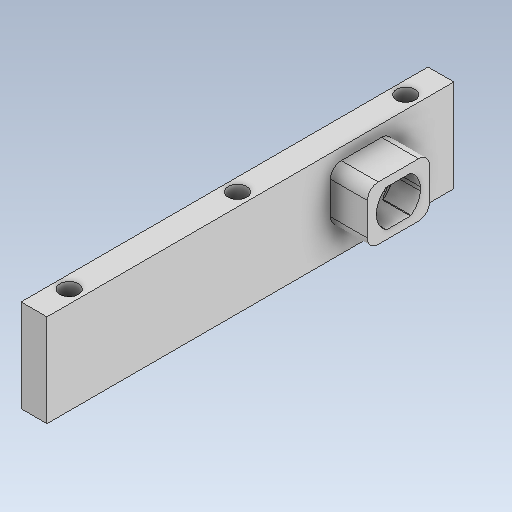
# Autodesk Inventor part: Innneseite_links
Saved by Autodesk Inventor 2026.4 (Build 304435030, 435C)
## iProperties
Created: 2026-11-20
Part Number: Innneseite_links
Material: Generisch
Document SubType Name: Modeling
Designer: weira
Density: 1 g/cm^3
Appearance: Vorgabe
Author: weira
Autodesk Inventor part; units mm, degrees
ref_plane "YZ Plane" through (0, 0, 0) normal (1, 0, 0) x (0, 1, 0)
ref_plane "XZ Plane" through (0, 0, 0) normal (0, 1, 0) x (-1, 0, 0)
ref_plane "XY Plane" through (0, 0, 0) normal (0, 0, 1) x (1, 0, 0)
sketch "Skizze1" plane through (0, 0, 0) normal (1, 0, 0) x (0, 1, 0)
  line L0 (-55, 12.5) -> (55, 12.5)
  line L1 (55, 12.5) -> (55, -12.5)
  line L2 (55, -12.5) -> (-55, -12.5)
  line L3 (-55, -12.5) -> (-55, 12.5)
  line L4 (-55, 12.5) -> (55, -12.5) construction
  line L5 (55, 12.5) -> (-55, -12.5) construction
  point P0 (0, 0)
  dimension "d0" = 25
  dimension "d1" = 110
  constraints: 12 end point, 2 midpoint, 2 parallel, 1 horizontal, 1 perpendicular
  measures "d0" distance between parallel lines of L2 L0
  measures "d1" distance of L0.start L0.end
extrude "Extrusion1" add sketch "Skizze1" along normal blind 7
sketch "Skizze2" plane through (0, 0, 0) normal (-1, 0, 0) x (0, 0, 1)
  line L0 (-12.5, -55) -> (-12.5, 55) projected
  line L1 (12.5, -55) -> (-12.5, -55) projected
  line L2 (12.5, 55) -> (12.5, -55) projected
  line L3 (-12.5, 55) -> (12.5, 55) projected
  line L4 (16.5, -55) -> (16.5, 55)
  line L5 (16.5, 55) -> (-12.5, 55)
  line L6 (-12.5, 55) -> (-12.5, -55)
  line L7 (-12.5, -55) -> (16.5, -55)
  circle A0 centre (2, -30) radius 8.5
  circle A1 centre (2, 30) radius 8.5
  circle A2 centre (2, -30) radius 19 construction
  circle A3 centre (2, 30) radius 19 construction
  line L8 (-12.5, 55) -> (16.5, 55)
  line L9 (16.5, 55) -> (16.5, 50)
  line L10 (16.5, 50) -> (-12.5, 50)
  line L11 (-12.5, 50) -> (-12.5, 55)
  line L12 (16.5, -55) -> (16.5, 55)
  line L13 (-12.5, -55) -> (16.5, -55)
  line L14 (16.5, -55) -> (16.5, -50)
  line L15 (16.5, -50) -> (-12.5, -50)
  line L16 (-12.5, -50) -> (-12.5, -55)
  circle A4 centre (2, -30) radius 20
  circle A5 centre (2, 30) radius 20
  circle A6 centre (2, -30) radius 6.5
  circle A7 centre (2, 30) radius 6.5
  point P0 (0, 0)
  point P1 (0, 0)
  point P2 (2, 49)
  dimension "d10" = 38
  dimension "d4" = 14.5
  dimension "d5" = 14.5
  dimension "d6" = 29
  dimension "d7" = 17
  dimension "d8" = 17
  dimension "d9" = 38
  dimension "d11" = 60
  dimension "d12" = 25
  dimension "d13" = 110
  dimension "d14" = 5
  dimension "d15" = 5
  dimension "d16" = 40
  dimension "d17" = 13
  dimension "d18" = 13
  dimension "d71" = 14.5
  constraints: 26 end point, 9 coincident, 7 centre point, 4 parallel, 2 horizontal, 2 perpendicular, 2 point on line, 1 vertical alignment, 2 other
  measures "d4" distance from line of L4 point (2, -30)
  measures "d5" distance from line of L4 point (2, 30)
  measures "d6" distance between parallel lines of L4 L6
  measures "d7" diameter of A0
  measures "d8" diameter of A1
  measures "d9" diameter of A2
  measures "d11" distance of A1.centre A0.centre
  measures "d12" distance from line of L7 A0.centre
  measures "d13" distance of L4.start L4.end
  measures "d14" distance between parallel lines of L5 L10
  measures "d15" distance between parallel lines of L7 L15
  measures "d16" diameter of A4
  measures "d17" diameter of A7
  measures "d18" diameter of A6
  measures "d71" distance from line of L6 A0.centre
extrude "Extrusion2" cut sketch "Skizze2" against normal blind 5 contours A0 | A6
extrude "Extrusion3" cut sketch "Skizze2" against normal blind 5.2 contours A6
sketch "Skizze3" plane through (0, -55, 12.5) normal (0, 0, 1) x (1, 0, 0)
  line L0 (5, 76.5) -> (5, 93.5) projected
  line L1 (0, 110) -> (0, 0) projected
  line L2 (0, 0) -> (7, 0) projected
  line L3 (7, 110) -> (7, 0) projected
  line L4 (0, 110) -> (7, 110) projected
  line L5 (0, 110) -> (0, 0)
  line L6 (0, 0) -> (7, 0)
  line L7 (7, 110) -> (7, 0)
  line L8 (0, 110) -> (7, 110)
  line L9 (3.5, 0) -> (3.5, 110) construction
  line L10 (2, 93.5) -> (2, 76.5)
  line L11 (2, 33.5) -> (2, 16.5)
  circle A0 centre (3.5, 100.5) radius 2.5 construction
  circle A1 centre (3.5, 9.5) radius 2.5 construction
  line L12 (0, 110) -> (7, 110)
  line L13 (0, 16.5) -> (7, 16.5) construction
  line L14 (0, 93.5) -> (7, 93.5) construction
  line L15 (0, 33.5) -> (7, 33.5) construction
  line L16 (0, 0) -> (0, 110)
  line L17 (0, 76.5) -> (7, 76.5) construction
  line L18 (0, 55) -> (7, 55) construction
  point P0 (0, 55)
  point P1 (3.5, 55)
  dimension "d23" = 7
  dimension "d24" = 3.5
  dimension "d25" = 110
  dimension "d26" = 55
  dimension "d27" = 5
  dimension "d28" = 5
  dimension "d29" = 9.5
  dimension "d30" = 9.5
  constraints: 28 end point, 10 point on line, 5 midpoint, 4 perpendicular, 3 coincident, 2 centre point
  measures "d23" distance between parallel lines of L7 L5
  measures "d24" distance between parallel lines of L5 L9
  measures "d25" distance of L7.start L6.end
  measures "d26" distance from line of L8 point (3.5, 55)
  measures "d27" diameter of A0
  measures "d28" diameter of A1
  measures "d29" distance from line of L6 A1.centre
  measures "d30" distance of point (3.5, 110) A0.centre
hole "Bohrung1" at (3.5, -45.5, 12.5) at (3.5, 45.5, 12.5) at (3.5, 0, 12.5) direction (0, 0, -1) diameter 5 end through all
sketch "Skizze4" plane through (7, 0, 0) normal (1, 0, 0) x (0, 0, -1)
  circle A0 centre (-2, -30) radius 8.5 projected
  line L0 (12.5, -55) -> (12.5, 55) projected
  line L1 (12.5, 55) -> (-12.5, 55) projected
  line L2 (-12.5, 55) -> (-12.5, -55) projected
  line L3 (-12.5, -55) -> (12.5, -55) projected
  line L4 (12.5, 2.2123) -> (12.5, 55)
  arc A1 (-1.4961, 66.3758) -> (-0.9961, 66.8758) centre (-1.4961, 66.8758) ccw
  line L5 (-0.9961, 66.8758) -> (-0.9961, 77.7758)
  arc A2 (-0.9961, 77.7758) -> (-1.4961, 78.2758) centre (-1.4961, 77.7758) ccw
  line L6 (-1.4961, 78.2758) -> (-10.2961, 78.2758)
  arc A3 (-10.2961, 78.2758) -> (-10.7961, 77.7758) centre (-10.2961, 77.7758) ccw
  line L7 (-10.7961, 77.7758) -> (-10.7961, 66.8758)
  arc A4 (-10.7961, 66.8758) -> (-10.2961, 66.3758) centre (-10.2961, 66.8758) ccw
  line L8 (-10.2961, 66.3758) -> (-1.4961, 66.3758)
  circle A5 centre (-8.8961, 76.3258) radius 1.325
  spline S0 degree 3 poles (-5.8961, 74.3258) (-5.645, 74.3258) (-5.4271, 74.2764) (-5.2521, 74.216) (-4.8953, 74.0929) (-4.5738, 73.8767) (-4.3311, 73.5726) (-4.0743, 73.2508) (-3.9035, 72.8091) (-3.8946, 72.3458) (-3.8918, 72.2003) (-3.9043, 72.0437) (-3.9417, 71.8796) (-4.0535, 71.3894) (-4.3969, 70.9004) (-4.8518, 70.6194) (-4.9087, 70.5843) (-4.9674, 70.5521) (-5.0276, 70.5231) (-5.1545, 70.462) (-5.2876, 70.4155) (-5.4237, 70.3831) (-5.5782, 70.3464) (-5.7372, 70.3278) (-5.8961, 70.3274) (-6.1602, 70.3267) (-6.4255, 70.3762) (-6.67, 70.4776) (-6.7025, 70.491) (-6.7341, 70.5052) (-6.7648, 70.52) (-7.234, 70.7459) (-7.4825, 71.0484) (-7.6694, 71.4044) (-7.7488, 71.5557) (-7.8087, 71.7159) (-7.8461, 71.8796) (-7.9389, 72.2862) (-7.9012, 72.7199) (-7.7285, 73.1243) (-7.6663, 73.2701) (-7.5811, 73.4236) (-7.4622, 73.5728) (-7.1454, 73.9706) (-6.6216, 74.2624) (-6.0869, 74.3162) (-6.0516, 74.3197) (-6.0163, 74.3223) (-5.981, 74.3239) (-5.9523, 74.3252) (-5.924, 74.3258) (-5.8961, 74.3258) knots 0.733383 0.733383 0.733383 0.733383 0.811921 0.811921 0.811921 0.972038 0.972038 0.972038 1.141536 1.141536 1.141536 1.194769 1.194769 1.194769 1.353829 1.353829 1.353829 1.373715 1.373715 1.373715 1.415683 1.415683 1.415683 1.46334 1.46334 1.46334 1.542576 1.542576 1.542576 1.553105 1.553105 1.553105 1.714156 1.714156 1.714156 1.782613 1.782613 1.782613 1.952625 1.952625 1.952625 2.013895 2.013895 2.013895 2.177242 2.177242 2.177242 2.187997 2.187997 2.187997 2.196723 2.196723 2.196723 2.196723
  circle A6 centre (-2.8961, 68.3258) radius 1.325
  arc A7 (-6.4, 35.95) -> (-6.9, 35.45) centre (-6.4, 35.45) ccw
  circle A8 centre (-5, 34) radius 1.325
  circle A9 centre (1, 26) radius 1.325
  arc A10 (-6.9, 24.55) -> (-6.4, 24.05) centre (-6.4, 24.55) ccw
  arc A11 (2.9, 35.45) -> (2.4, 35.95) centre (2.4, 35.45) ccw
  arc A12 (2.4, 24.05) -> (2.9, 24.55) centre (2.4, 24.55) ccw
  spline S1 degree 3 poles (-2, 32) (-1.749, 32) (-1.531, 31.9506) (-1.356, 31.8902) (-0.9992, 31.7671) (-0.6777, 31.5509) (-0.4351, 31.2469) (-0.1782, 30.925) (-0.0074, 30.4833) (0.0014, 30.02) (0.0042, 29.8745) (-0.0082, 29.7179) (-0.0456, 29.5538) (-0.1575, 29.0636) (-0.5009, 28.5747) (-0.9557, 28.2937) (-1.0126, 28.2585) (-1.0713, 28.2263) (-1.1315, 28.1973) (-1.2584, 28.1362) (-1.3915, 28.0897) (-1.5276, 28.0573) (-1.6821, 28.0206) (-1.8411, 28.002) (-2, 28.0016) (-2.2641, 28.0009) (-2.5294, 28.0504) (-2.7739, 28.1518) (-2.8064, 28.1652) (-2.838, 28.1794) (-2.8687, 28.1942) (-3.3379, 28.4201) (-3.5864, 28.7226) (-3.7733, 29.0786) (-3.8527, 29.2299) (-3.9126, 29.3901) (-3.95, 29.5538) (-4.0429, 29.9604) (-4.0051, 30.3941) (-3.8324, 30.7986) (-3.7702, 30.9443) (-3.685, 31.0978) (-3.5661, 31.247) (-3.2493, 31.6448) (-2.7255, 31.9366) (-2.1908, 31.9904) (-2.1556, 31.9939) (-2.1203, 31.9965) (-2.0849, 31.9981) (-2.0562, 31.9994) (-2.0279, 32) (-2, 32) knots 0.733383 0.733383 0.733383 0.733383 0.811921 0.811921 0.811921 0.972038 0.972038 0.972038 1.141536 1.141536 1.141536 1.194769 1.194769 1.194769 1.353829 1.353829 1.353829 1.373715 1.373715 1.373715 1.415683 1.415683 1.415683 1.46334 1.46334 1.46334 1.542576 1.542576 1.542576 1.553105 1.553105 1.553105 1.714156 1.714156 1.714156 1.782613 1.782613 1.782613 1.952625 1.952625 1.952625 2.013895 2.013895 2.013895 2.177242 2.177242 2.177242 2.187997 2.187997 2.187997 2.196723 2.196723 2.196723 2.196723
  line L9 (-6.4, 24.05) -> (2.4, 24.05)
  line L10 (2.4, 35.95) -> (-6.4, 35.95)
  line L11 (2.9, 24.55) -> (2.9, 35.45)
  line L12 (-6.9, 35.45) -> (-6.9, 24.55)
  point P0 (0, 0)
  point P1 (-2, 30)
  point P2 (-5.8961, 72.3258)
  point P3 (-5.8961, 74.3258)
  point P4 (-2, 30)
  point P5 (-2, 32)
  dimension "d42" = 25
  dimension "d72" = 60
  dimension "d73" = 14.5
  constraints: 18 end point, 16 point on circle, 12 centre point, 2 other
  measures "d42" distance of L0.end L1.end
  measures "d72" distance of A0.centre point (-2, 30)
  measures "d73" distance from line of L0 point (-2, 30)
extrude "Extrusion4" cut sketch "Skizze4" against normal through all contours L10 A11 L11 A12 L9 A10 L12 A7 | A8 | A9 | S1
sketch "Skizze5" plane through (7, 0, 0) normal (1, 0, 0) x (0, 0, -1)
  line L0 (2.9, 35.45) -> (2.9, 24.55) projected
  arc A0 (2.4, 24.05) -> (2.9, 24.55) centre (2.4, 24.55) ccw projected
  line L1 (2.4, 24.05) -> (-6.4, 24.05) projected
  arc A1 (-6.9, 24.55) -> (-6.4, 24.05) centre (-6.4, 24.55) ccw projected
  line L2 (-6.9, 24.55) -> (-6.9, 35.45) projected
  arc A2 (-6.4, 35.95) -> (-6.9, 35.45) centre (-6.4, 35.45) ccw projected
  line L3 (-6.4, 35.95) -> (2.4, 35.95) projected
  arc A3 (2.9, 35.45) -> (2.4, 35.95) centre (2.4, 35.45) ccw projected
  line L4 (12.5, -55) -> (12.5, 55) projected
  line L5 (12.5, 55) -> (-12.5, 55) projected
  line L6 (-12.5, 55) -> (-12.5, -55) projected
  line L7 (-12.5, -55) -> (12.5, -55) projected
  line L8 (-9.3, 35.45) -> (-9.3, 24.55)
  arc A4 (-9.3, 24.55) -> (-6.4, 21.65) centre (-6.4, 24.55) ccw
  line L9 (-6.4, 21.65) -> (2.4, 21.65)
  arc A5 (2.4, 21.65) -> (5.3, 24.55) centre (2.4, 24.55) ccw
  line L10 (5.3, 24.55) -> (5.3, 35.45)
  arc A6 (5.3, 35.45) -> (2.4, 38.35) centre (2.4, 35.45) ccw
  line L11 (2.4, 38.35) -> (-6.4, 38.35)
  arc A7 (-6.4, 38.35) -> (-9.3, 35.45) centre (-6.4, 35.45) ccw
  point P0 (0, 0)
  dimension "d74" = 2.4
  constraints: 8 end point, 8 point on circle, 4 centre point, 7 other
  measures "d74" distance between parallel lines of L2 L8
extrude "Extrusion5" add sketch "Skizze5" along normal blind 1.9 contours A7 L11 A6 L10 A5 L9 A4 L8
sketch "Skizze6" plane through (8.9, 0, 0) normal (1, 0, 0) x (0, 0, -1)
  spline S0 degree 3 poles (1.1324, 61.7724) (2.9383, 61.9247) (4.6477, 62.9496) (5.6324, 64.4761) knots 0 0 0 0 1 1 1 1
  spline S1 degree 3 poles (0.1324, 61.7724) (0.2987, 61.7584) (0.4655, 61.7514) (0.7993, 61.7514) (0.9661, 61.7584) (1.1324, 61.7724) knots 0 0 0 0 0.5 0.5 1 1 1 1
  spline S2 degree 3 poles (-4.3676, 64.4761) (-3.3829, 62.9496) (-1.6736, 61.9247) (0.1324, 61.7724) knots 0 0 0 0 1 1 1 1
  line L0 (5.6324, 64.4761) -> (5.6324, 70.9267)
  spline S3 degree 3 poles (5.6324, 70.9267) (4.6477, 72.4532) (2.9383, 73.4781) (1.1324, 73.6304) knots 0 0 0 0 1 1 1 1
  spline S4 degree 3 poles (0.1324, 73.6304) (-1.6736, 73.4781) (-3.3829, 72.4532) (-4.3676, 70.9267) knots 0 0 0 0 1 1 1 1
  line L1 (-4.3676, 70.9267) -> (-4.3676, 64.4761)
  spline S5 degree 3 poles (1.1324, 73.6304) (0.9661, 73.6444) (0.7993, 73.6514) (0.4655, 73.6514) (0.2987, 73.6444) (0.1324, 73.6304) knots 0 0 0 0 0.5 0.5 1 1 1 1
  line L2 (-28.2501, 0.1383) -> (-27.7556, -0.2574) construction
  spline S6 degree 3 poles (-16.7641, 79.1019) (-16.9304, 79.1159) (-17.0972, 79.1229) (-17.431, 79.1229) (-17.5978, 79.1159) (-17.7641, 79.1019) knots 0 0 0 0 0.5 0.5 1 1 1 1
  spline S7 degree 3 poles (-17.7641, 79.1019) (-19.5701, 78.9496) (-21.2794, 77.9247) (-22.2641, 76.3982) knots 0 0 0 0 1 1 1 1
  spline S8 degree 3 poles (-12.2641, 76.3982) (-13.2488, 77.9247) (-14.9582, 78.9496) (-16.7641, 79.1019) knots 0 0 0 0 1 1 1 1
  line L3 (-22.2641, 76.3982) -> (-22.2641, 69.9476)
  spline S9 degree 3 poles (-17.7641, 67.244) (-17.5978, 67.2299) (-17.431, 67.2229) (-17.0972, 67.2229) (-16.9304, 67.2299) (-16.7641, 67.244) knots 0 0 0 0 0.5 0.5 1 1 1 1
  spline S10 degree 3 poles (-22.2641, 69.9476) (-21.2794, 68.4211) (-19.5701, 67.3963) (-17.7641, 67.244) knots 0 0 0 0 1 1 1 1
  spline S11 degree 3 poles (-16.7641, 67.244) (-14.9582, 67.3963) (-13.2488, 68.4211) (-12.2641, 69.9476) knots 0 0 0 0 1 1 1 1
  line L4 (-12.2641, 69.9476) -> (-12.2641, 76.3982)
  line L5 (-17.2641, 73.1729) -> (-15.0095, 73.1729) construction
  line L6 (-17.2641, 73.1729) -> (-17.2641, 69.8514) construction
  line L7 (-12.3641, 69.2746) -> (-15.396, 67.2229)
  line L8 (-22.1641, 69.2746) -> (-19.1323, 67.2229)
  line L9 (-12.3641, 77.0713) -> (-15.396, 79.1229)
  line L10 (-22.1641, 77.0713) -> (-19.1323, 79.1229)
  line L11 (-12.8641, 67.7229) -> (-21.6641, 78.6229) construction
  line L12 (-12.8641, 78.6229) -> (-21.6641, 67.7229) construction
  arc A0 (-9.3, 24.55) -> (-6.4, 21.65) centre (-6.4, 24.55) ccw
  line L13 (-6.4, 21.65) -> (2.4, 21.65)
  arc A1 (2.4, 21.65) -> (5.3, 24.55) centre (2.4, 24.55) ccw
  line L14 (5.3, 24.55) -> (5.3, 35.45)
  arc A2 (5.3, 35.45) -> (2.4, 38.35) centre (2.4, 35.45) ccw
  line L15 (2.4, 38.35) -> (-6.4, 38.35)
  arc A3 (-6.4, 38.35) -> (-9.3, 35.45) centre (-6.4, 35.45) ccw
  line L16 (-9.3, 35.45) -> (-9.3, 24.55)
  line L17 (-6.4, 35.95) -> (2.4, 35.95)
  arc A4 (2.9, 35.45) -> (2.4, 35.95) centre (2.4, 35.45) ccw
  line L18 (2.9, 35.45) -> (2.9, 24.55)
  arc A5 (2.4, 24.05) -> (2.9, 24.55) centre (2.4, 24.55) ccw
  line L19 (2.4, 24.05) -> (-6.4, 24.05)
  arc A6 (-6.9, 24.55) -> (-6.4, 24.05) centre (-6.4, 24.55) ccw
  line L20 (-6.9, 24.55) -> (-6.9, 35.45)
  arc A7 (-6.4, 35.95) -> (-6.9, 35.45) centre (-6.4, 35.45) ccw
  line L21 (-6.4, 24.55) -> (2.4, 35.45) construction
  line L22 (2.4, 24.55) -> (-6.4, 35.45) construction
  spline S12 degree 3 poles (-2.5, 24.071) (-2.3337, 24.057) (-2.1669, 24.05) (-1.8331, 24.05) (-1.6663, 24.057) (-1.5, 24.071) knots 0 0 0 0 0.5 0.5 1 1 1 1
  spline S13 degree 3 poles (-1.5, 24.071) (0.306, 24.2233) (2.0153, 25.2482) (3, 26.7747) knots 0 0 0 0 1 1 1 1
  line L23 (-2, 30) -> (0.2547, 30) construction
  line L24 (-2, 30) -> (-2, 26.6784) construction
  line L25 (-6.9, 26.1017) -> (-3.8681, 24.05)
  spline S14 degree 3 poles (-7, 26.7747) (-6.0153, 25.2482) (-4.306, 24.2234) (-2.5, 24.071) knots 0 0 0 0 1 1 1 1
  line L26 (3, 26.7747) -> (3, 33.2253)
  line L27 (2.9, 33.8983) -> (-0.1319, 35.95)
  spline S15 degree 3 poles (3, 33.2253) (2.0153, 34.7518) (0.306, 35.7767) (-1.5, 35.929) knots 0 0 0 0 1 1 1 1
  line L28 (2.4, 24.55) -> (-6.4, 35.45) construction
  line L29 (2.4, 35.45) -> (-6.4, 24.55) construction
  spline S16 degree 3 poles (-1.5, 35.929) (-1.6663, 35.943) (-1.8331, 35.95) (-2.1669, 35.95) (-2.3337, 35.943) (-2.5, 35.929) knots 0 0 0 0 0.5 0.5 1 1 1 1
  spline S17 degree 3 poles (-2.5, 35.929) (-4.306, 35.7766) (-6.0153, 34.7518) (-7, 33.2253) knots 0 0 0 0 1 1 1 1
  line L30 (-7, 33.2253) -> (-7, 26.7747)
  line L31 (2.9, 26.1017) -> (-0.1319, 24.05)
  line L32 (-6.9, 33.8983) -> (-3.8681, 35.95)
  point P0 (0, 0)
  point P1 (0.6324, 67.7014)
  point P2 (-28.0028, -0.0595)
  point P3 (-17.2641, 73.1729)
  point P4 (-2, 30)
  point P5 (-2, 30)
  point P6 (2.9, 33.375)
  point P7 (2.9, 26.625)
  point P8 (-6.9, 26.625)
  point P9 (-6.9, 33.375)
  constraints: 50 end point, 12 symmetric about line, 6 horizontal alignment, 4 midpoint, 48 other
extrude "Extrusion6" cut sketch "Skizze6" against normal through all contours S16 S15 L18 S13 S12 S14 L20 S17 | L20 S14 L30 S17 | S15 L26 S13 L18
extrude "Extrusion7" add sketch "Skizze6" along normal blind 0.2 contours L16 A3 L15 A2 L14 A1 L13 A0 | L17 L32 L20 A7 | L17 A4 L18 L27 | L25 L19 A6 L20 | L18 A5 L19 L31
sketch "Skizze8" plane through (5, -30, 2) normal (-1, 0, 0) x (0, 0, 1)
  circle A0 centre (0, 0) radius 6.5 projected
  circle A1 centre (0, 0) radius 8.5 projected
  line L0 (8.5, 0) -> (2.6266, -8.084)
  line L1 (2.6266, -8.084) -> (-6.8766, -4.9962)
  line L2 (-6.8766, -4.9962) -> (-6.8766, 4.9962)
  line L3 (-6.8766, 4.9962) -> (2.6266, 8.084)
  line L4 (2.6266, 8.084) -> (8.5, 0)
  point P0 (-2, 30)
  constraints: 10 end point, 1 coincident, 1 horizontal alignment, 12 other
extrude "Extrusion9" cut sketch "Skizze8" against normal up to surface (0.2 mm away) contours L0 L1 L2 L3 L4
sketch "Skizze9" plane through (9.1, 0, 0) normal (1, 0, 0) x (0, 0, -1)
  line L0 (-6.4, 21.65) -> (2.4, 21.65)
  arc A0 (2.4, 21.65) -> (5.3, 24.55) centre (2.4, 24.55) ccw
  line L1 (5.3, 24.55) -> (5.3, 35.45)
  arc A1 (5.3, 35.45) -> (2.4, 38.35) centre (2.4, 35.45) ccw
  line L2 (2.4, 38.35) -> (-6.4, 38.35)
  arc A2 (-6.4, 38.35) -> (-9.3, 35.45) centre (-6.4, 35.45) ccw
  line L3 (-9.3, 35.45) -> (-9.3, 24.55)
  arc A3 (-9.3, 24.55) -> (-6.4, 21.65) centre (-6.4, 24.55) ccw
  line L4 (-3.8681, 35.95) -> (-0.1319, 35.95)
  line L5 (-0.1319, 35.95) -> (2.9, 33.8983)
  line L6 (2.9, 33.8983) -> (2.9, 33.375)
  arc A4 (3, 33.2253) -> (2.9, 33.375) centre (-1.7435, 30.1653) ccw
  line L7 (3, 33.2253) -> (3, 26.7747)
  arc A5 (2.9, 26.625) -> (3, 26.7747) centre (-1.7435, 29.8347) ccw
  line L8 (2.9, 26.625) -> (2.9, 26.1017)
  line L9 (2.9, 26.1017) -> (-0.1319, 24.05)
  line L10 (-0.1319, 24.05) -> (-3.8681, 24.05)
  line L11 (-3.8681, 24.05) -> (-6.9, 26.1017)
  line L12 (-6.9, 26.1017) -> (-6.9, 26.625)
  arc A6 (-7, 26.7747) -> (-6.9, 26.625) centre (-2.2565, 29.8348) ccw
  line L13 (-7, 26.7747) -> (-7, 33.2253)
  arc A7 (-6.9, 33.375) -> (-7, 33.2253) centre (-2.2564, 30.1651) ccw
  line L14 (-6.9, 33.375) -> (-6.9, 33.8983)
  line L15 (-6.9, 33.8983) -> (-3.8681, 35.95)
  spline S0 degree 3 poles (10.6773, 97.9027) (12.4832, 98.055) (14.1926, 99.0799) (15.1773, 100.6064) knots 0 0 0 0 1 1 1 1
  spline S1 degree 3 poles (9.6773, 97.9027) (9.8436, 97.8887) (10.0104, 97.8817) (10.3442, 97.8817) (10.511, 97.8887) (10.6773, 97.9027) knots 0 0 0 0 0.5 0.5 1 1 1 1
  spline S2 degree 3 poles (5.1773, 100.6064) (6.162, 99.0799) (7.8713, 98.055) (9.6773, 97.9027) knots 0 0 0 0 1 1 1 1
  line L16 (15.1773, 100.6064) -> (15.1773, 107.057)
  spline S3 degree 3 poles (15.1773, 107.057) (14.1926, 108.5835) (12.4832, 109.6084) (10.6773, 109.7607) knots 0 0 0 0 1 1 1 1
  spline S4 degree 3 poles (9.6773, 109.7607) (7.8713, 109.6084) (6.162, 108.5835) (5.1773, 107.057) knots 0 0 0 0 1 1 1 1
  line L17 (5.1773, 107.057) -> (5.1773, 100.6064)
  spline S5 degree 3 poles (10.6773, 109.7607) (10.511, 109.7747) (10.3442, 109.7817) (10.0104, 109.7817) (9.8436, 109.7747) (9.6773, 109.7607) knots 0 0 0 0 0.5 0.5 1 1 1 1
  line L18 (-18.7052, 36.2686) -> (-18.2107, 35.8729) construction
  spline S6 degree 3 poles (-8.2192, 103.3743) (-8.053, 103.3602) (-7.8861, 103.3532) (-7.5523, 103.3532) (-7.3855, 103.3602) (-7.2192, 103.3743) knots 0 0 0 0 0.5 0.5 1 1 1 1
  spline S7 degree 3 poles (-7.2192, 103.3743) (-5.4133, 103.5266) (-3.7039, 104.5514) (-2.7192, 106.0779) knots 0 0 0 0 1 1 1 1
  line L19 (-7.7192, 109.3032) -> (-5.4646, 109.3032) construction
  line L20 (-7.7192, 109.3032) -> (-7.7192, 105.9817) construction
  line L21 (-12.6192, 105.4049) -> (-9.5874, 103.3532)
  spline S8 degree 3 poles (-12.7192, 106.0779) (-11.7345, 104.5514) (-10.0252, 103.5266) (-8.2192, 103.3743) knots 0 0 0 0 1 1 1 1
  line L22 (-2.7192, 106.0779) -> (-2.7192, 112.5285)
  line L23 (-2.8192, 113.2016) -> (-5.8511, 115.2532)
  spline S9 degree 3 poles (-2.7192, 112.5285) (-3.7039, 114.055) (-5.4133, 115.0799) (-7.2192, 115.2322) knots 0 0 0 0 1 1 1 1
  line L24 (-3.3192, 103.8532) -> (-12.1192, 114.7532) construction
  line L25 (-3.3192, 114.7532) -> (-12.1192, 103.8532) construction
  spline S10 degree 3 poles (-7.2192, 115.2322) (-7.3855, 115.2462) (-7.5523, 115.2532) (-7.8861, 115.2532) (-8.053, 115.2462) (-8.2192, 115.2322) knots 0 0 0 0 0.5 0.5 1 1 1 1
  spline S11 degree 3 poles (-8.2192, 115.2322) (-10.0252, 115.0799) (-11.7345, 114.055) (-12.7192, 112.5285) knots 0 0 0 0 1 1 1 1
  line L26 (-12.7192, 112.5285) -> (-12.7192, 106.0779)
  line L27 (-2.8192, 105.4049) -> (-5.8511, 103.3532)
  line L28 (-12.6192, 113.2016) -> (-9.5874, 115.2532)
  arc A8 (0.2449, 60.6803) -> (3.1449, 57.7803) centre (3.1449, 60.6803) ccw
  line L29 (3.1449, 57.7803) -> (11.9449, 57.7803)
  arc A9 (11.9449, 57.7803) -> (14.8449, 60.6803) centre (11.9449, 60.6803) ccw
  line L30 (14.8449, 60.6803) -> (14.8449, 71.5803)
  arc A10 (14.8449, 71.5803) -> (11.9449, 74.4803) centre (11.9449, 71.5803) ccw
  line L31 (11.9449, 74.4803) -> (3.1449, 74.4803)
  arc A11 (3.1449, 74.4803) -> (0.2449, 71.5803) centre (3.1449, 71.5803) ccw
  line L32 (0.2449, 71.5803) -> (0.2449, 60.6803)
  line L33 (3.1449, 72.0803) -> (11.9449, 72.0803)
  arc A12 (12.4449, 71.5803) -> (11.9449, 72.0803) centre (11.9449, 71.5803) ccw
  line L34 (12.4449, 71.5803) -> (12.4449, 60.6803)
  arc A13 (11.9449, 60.1803) -> (12.4449, 60.6803) centre (11.9449, 60.6803) ccw
  line L35 (11.9449, 60.1803) -> (3.1449, 60.1803)
  arc A14 (2.6449, 60.6803) -> (3.1449, 60.1803) centre (3.1449, 60.6803) ccw
  line L36 (2.6449, 60.6803) -> (2.6449, 71.5803)
  arc A15 (3.1449, 72.0803) -> (2.6449, 71.5803) centre (3.1449, 71.5803) ccw
  line L37 (3.1449, 60.6803) -> (11.9449, 71.5803) construction
  line L38 (11.9449, 60.6803) -> (3.1449, 71.5803) construction
  line L39 (2.6449, 70.0286) -> (5.6768, 72.0803)
  spline S12 degree 3 poles (7.0449, 72.0593) (5.2389, 71.9069) (3.5296, 70.8821) (2.5449, 69.3556) knots 0 0 0 0 1 1 1 1
  spline S13 degree 3 poles (8.0449, 72.0593) (7.8786, 72.0733) (7.7118, 72.0803) (7.378, 72.0803) (7.2112, 72.0733) (7.0449, 72.0593) knots 0 0 0 0 0.5 0.5 1 1 1 1
  spline S14 degree 3 poles (12.5449, 69.3556) (11.5602, 70.8821) (9.8509, 71.907) (8.0449, 72.0593) knots 0 0 0 0 1 1 1 1
  line L40 (12.4449, 70.0286) -> (9.413, 72.0803)
  line L41 (7.5449, 66.1303) -> (9.7995, 66.1303) construction
  line L42 (12.5449, 62.905) -> (12.5449, 69.3556)
  line L43 (2.5449, 69.3556) -> (2.5449, 62.905)
  line L44 (11.9449, 71.5803) -> (3.1449, 60.6803) construction
  line L45 (11.9449, 60.6803) -> (3.1449, 71.5803) construction
  line L46 (7.5449, 66.1303) -> (7.5449, 62.8087) construction
  spline S15 degree 3 poles (7.0449, 60.2013) (7.2112, 60.1873) (7.378, 60.1803) (7.7118, 60.1803) (7.8786, 60.1873) (8.0449, 60.2013) knots 0 0 0 0 0.5 0.5 1 1 1 1
  line L47 (2.6449, 62.232) -> (5.6768, 60.1803)
  spline S16 degree 3 poles (2.5449, 62.905) (3.5296, 61.3785) (5.2389, 60.3537) (7.0449, 60.2013) knots 0 0 0 0 1 1 1 1
  line L48 (12.4449, 62.232) -> (9.413, 60.1803)
  spline S17 degree 3 poles (8.0449, 60.2013) (9.8509, 60.3536) (11.5602, 61.3785) (12.5449, 62.905) knots 0 0 0 0 1 1 1 1
  arc A16 (-9.3, 24.55) -> (-6.4, 21.65) centre (-6.4, 24.55) ccw
  line L49 (-6.4, 21.65) -> (2.4, 21.65)
  arc A17 (2.4, 21.65) -> (5.3, 24.55) centre (2.4, 24.55) ccw
  line L50 (5.3, 24.55) -> (5.3, 35.45)
  arc A18 (5.3, 35.45) -> (2.4, 38.35) centre (2.4, 35.45) ccw
  line L51 (2.4, 38.35) -> (-6.4, 38.35)
  arc A19 (-6.4, 38.35) -> (-9.3, 35.45) centre (-6.4, 35.45) ccw
  line L52 (-9.3, 35.45) -> (-9.3, 24.55)
  line L53 (-6.4, 35.95) -> (2.4, 35.95)
  arc A20 (2.9, 35.45) -> (2.4, 35.95) centre (2.4, 35.45) ccw
  line L54 (2.9, 35.45) -> (2.9, 24.55)
  arc A21 (2.4, 24.05) -> (2.9, 24.55) centre (2.4, 24.55) ccw
  line L55 (2.4, 24.05) -> (-6.4, 24.05)
  arc A22 (-6.9, 24.55) -> (-6.4, 24.05) centre (-6.4, 24.55) ccw
  line L56 (-6.9, 24.55) -> (-6.9, 35.45)
  arc A23 (-6.4, 35.95) -> (-6.9, 35.45) centre (-6.4, 35.45) ccw
  line L57 (-6.4, 24.55) -> (2.4, 35.45) construction
  line L58 (2.4, 24.55) -> (-6.4, 35.45) construction
  line L59 (-6.9, 33.8983) -> (-3.8681, 35.95)
  spline S18 degree 3 poles (-2.5, 35.929) (-4.306, 35.7766) (-6.0153, 34.7518) (-7, 33.2253) knots 0 0 0 0 1 1 1 1
  spline S19 degree 3 poles (-1.5, 35.929) (-1.6663, 35.943) (-1.8331, 35.95) (-2.1669, 35.95) (-2.3337, 35.943) (-2.5, 35.929) knots 0 0 0 0 0.5 0.5 1 1 1 1
  spline S20 degree 3 poles (3, 33.2253) (2.0153, 34.7518) (0.306, 35.7767) (-1.5, 35.929) knots 0 0 0 0 1 1 1 1
  line L60 (2.9, 33.8983) -> (-0.1319, 35.95)
  line L61 (-2, 30) -> (0.2547, 30) construction
  line L62 (3, 26.7747) -> (3, 33.2253)
  line L63 (-7, 33.2253) -> (-7, 26.7747)
  line L64 (2.4, 35.45) -> (-6.4, 24.55) construction
  line L65 (2.4, 24.55) -> (-6.4, 35.45) construction
  line L66 (-2, 30) -> (-2, 26.6784) construction
  spline S21 degree 3 poles (-2.5, 24.071) (-2.3337, 24.057) (-2.1669, 24.05) (-1.8331, 24.05) (-1.6663, 24.057) (-1.5, 24.071) knots 0 0 0 0 0.5 0.5 1 1 1 1
  line L67 (-6.9, 26.1017) -> (-3.8681, 24.05)
  spline S22 degree 3 poles (-7, 26.7747) (-6.0153, 25.2482) (-4.306, 24.2234) (-2.5, 24.071) knots 0 0 0 0 1 1 1 1
  line L68 (2.9, 26.1017) -> (-0.1319, 24.05)
  spline S23 degree 3 poles (-1.5, 24.071) (0.306, 24.2233) (2.0153, 25.2482) (3, 26.7747) knots 0 0 0 0 1 1 1 1
  point P0 (0, 0)
  point P1 (9.5449, 36.1303)
  point P2 (10.1773, 103.8317)
  point P3 (-18.4579, 36.0708)
  point P4 (-7.7192, 109.3032)
  point P5 (7.5449, 66.1303)
  point P6 (7.5449, 66.1303)
  point P7 (12.4449, 69.5053)
  point P8 (12.4449, 62.7553)
  point P9 (2.6449, 62.7553)
  point P10 (2.6449, 69.5053)
  point P11 (-2, 30)
  point P12 (-2, 30)
  point P13 (-6.9, 33.375)
  point P14 (2.9, 26.625)
  constraints: 106 end point, 32 point on circle, 18 symmetric about line, 16 centre point, 8 horizontal alignment, 6 midpoint, 64 other
extrude "Extrusion10" add sketch "Skizze9" along normal blind 7.9 contours A3 L3 A2 L2 A1 L1 A0 L0 | L4 S19 S18 L14 L15 | L15 L56 A23 L53 | L4 L5 L6 S20 S19 | L53 A20 L54 L5 | S22 S21 L10 L11 L12 | L8 L9 L10 S21 S23 | L11 L55 A22 L56 | L54 A21 L55 L9
sketch "Skizze10" plane through (0, 0, 0) normal (-1, 0, 0) x (0, 0, 1)
  spline S0 degree 5 poles (-3, 33.2253) (-2.9805, 33.2556) (-2.9607, 33.2857) (-2.9407, 33.3156) (-2.9205, 33.3454) (-2.9, 33.375) knots 0 0 0 0 0 0 1 1 1 1 1 1 projected
  line L0 (-2.9, 33.375) -> (-2.9, 35.45) projected
  arc A0 (-2.4, 35.95) -> (-2.9, 35.45) centre (-2.4, 35.45) ccw projected
  line L1 (-2.4, 35.95) -> (6.4, 35.95) projected
  arc A1 (6.9, 35.45) -> (6.4, 35.95) centre (6.4, 35.45) ccw projected
  line L2 (6.9, 35.45) -> (6.9, 33.375) projected
  spline S1 degree 5 poles (6.9, 33.375) (6.9205, 33.3454) (6.9407, 33.3156) (6.9607, 33.2857) (6.9805, 33.2556) (7, 33.2253) knots 0 0 0 0 0 0 1 1 1 1 1 1 projected
  line L3 (7, 33.2253) -> (7, 26.7747) projected
  spline S2 degree 5 poles (7, 26.7747) (6.9805, 26.7444) (6.9607, 26.7143) (6.9407, 26.6844) (6.9205, 26.6546) (6.9, 26.625) knots 0 0 0 0 0 0 1 1 1 1 1 1 projected
  line L4 (6.9, 26.625) -> (6.9, 24.55) projected
  arc A2 (6.4, 24.05) -> (6.9, 24.55) centre (6.4, 24.55) ccw projected
  line L5 (6.4, 24.05) -> (-2.4, 24.05) projected
  arc A3 (-2.9, 24.55) -> (-2.4, 24.05) centre (-2.4, 24.55) ccw projected
  line L6 (-2.9, 24.55) -> (-2.9, 26.625) projected
  spline S3 degree 5 poles (-2.9, 26.625) (-2.9205, 26.6546) (-2.9407, 26.6844) (-2.9607, 26.7143) (-2.9805, 26.7444) (-3, 26.7747) knots 0 0 0 0 0 0 1 1 1 1 1 1 projected
  line L7 (-3, 26.7747) -> (-3, 33.2253) projected
  circle A4 centre (2, -30) radius 8.5 projected
  line L8 (-12.5, -55) -> (-12.5, 55) projected
  line L9 (12.5, -55) -> (-12.5, -55) projected
  line L10 (12.5, 55) -> (12.5, -55) projected
  line L11 (-12.5, 55) -> (12.5, 55) projected
  line L12 (6.4, 35.45) -> (-2.4, 24.55) construction
  line L13 (6.4, 24.55) -> (-2.4, 35.45) construction
  line L14 (6.5, 36) -> (-2.5, 36)
  line L15 (-3, 35.5) -> (-3, 24.5)
  line L16 (-2.5, 24) -> (6.5, 24)
  line L17 (7, 24.5) -> (7, 35.5)
  line L18 (7, 36) -> (-3, 24) construction
  line L19 (-3, 36) -> (7, 24) construction
  arc A5 (7, 35.5) -> (6.5, 36) centre (6.5, 35.5) ccw
  arc A6 (-2.5, 36) -> (-3, 35.5) centre (-2.5, 35.5) ccw
  arc A7 (-3, 24.5) -> (-2.5, 24) centre (-2.5, 24.5) ccw
  arc A8 (6.5, 24) -> (7, 24.5) centre (6.5, 24.5) ccw
  point P0 (0, 0)
  point P1 (2, 30)
  point P2 (-3, 26.7747)
  point P3 (7, 26.7747)
  point P4 (7, 33.2253)
  point P5 (-3, 33.2253)
  dimension "d77" = 11.9
  dimension "d78" = 10
  dimension "d79" = 12
  dimension "d80" = 0.5
  dimension "d81" = 0.5
  constraints: 16 end point, 8 point on circle, 8 point on line, 8 tangent, 4 centre point, 3 midpoint, 2 equal radius, 2 parallel, 1 horizontal, 1 perpendicular, 4 other
  measures "d77" distance between parallel lines of L5 L1
  measures "d78" distance of L18.end L19.end
  measures "d79" distance between parallel lines of L16 L14
  measures "d80" radius of A5
  measures "d81" radius of A6
extrude "Extrusion11" cut sketch "Skizze10" against normal up to surface (8.9 mm away) contours L15 A6 L14 A5 L17 S1 L2 A1 L1 A0 L0 S0 | S3 L6 A3 L5 A2 L4 S2 L17 A8 L16 A7 L15
sketch "Skizze11" plane through (8.9, 0, 0) normal (-1, 0, 0) x (0, 0, 1)
  line L0 (6.9, 33.375) -> (6.9, 33.8983) projected
  line L1 (6.9, 33.8983) -> (3.8681, 35.95) projected
  line L2 (3.8681, 35.95) -> (2, 35.95) projected
  arc A0 (2.5, 35.929) -> (2, 35.95) centre (2, 30) ccw projected
  line L3 (-12.5, -55) -> (-12.5, 55) projected
  line L4 (12.5, -55) -> (-12.5, -55) projected
  line L5 (12.5, 55) -> (12.5, -55) projected
  line L6 (-12.5, 55) -> (12.5, 55) projected
  circle A1 centre (2, -30) radius 8.5 projected
  line L7 (7, 35.5) -> (7, 24.5) projected
  arc A2 (6.5, 24) -> (7, 24.5) centre (6.5, 24.5) ccw projected
  line L8 (6.5, 24) -> (-2.5, 24) projected
  arc A3 (-3, 24.5) -> (-2.5, 24) centre (-2.5, 24.5) ccw projected
  line L9 (-3, 24.5) -> (-3, 35.5) projected
  arc A4 (-2.5, 36) -> (-3, 35.5) centre (-2.5, 35.5) ccw projected
  line L10 (-2.5, 36) -> (6.5, 36) projected
  arc A5 (7, 35.5) -> (6.5, 36) centre (6.5, 35.5) ccw projected
  line L11 (3.8681, 35.95) -> (6.9, 33.8983)
  line L12 (3.8681, 24.05) -> (6.9, 26.1017) projected
  line L13 (6.9, 26.1017) -> (3.8681, 24.05)
  line L14 (0.1319, 35.95) -> (-2.9, 33.8983) projected
  line L15 (-2.9, 33.8983) -> (-2.9, 33.375) projected
  line L16 (0.1319, 35.95) -> (-2.9, 33.8983)
  line L17 (-2.9, 26.1017) -> (0.1319, 24.05) projected
  line L18 (-2.9, 26.1017) -> (0.1319, 24.05)
  line L19 (0.0522, 24.1039) -> (0.2058, 24)
  line L20 (-2.7902, 26.0274) -> (-3, 26.1693)
  line L21 (-2.7317, 34.0122) -> (-3, 33.8307)
  line L22 (0.0764, 35.9125) -> (0.2058, 36)
  line L23 (4.0667, 35.8156) -> (3.7942, 36)
  line L24 (6.8158, 33.9553) -> (7, 33.8307)
  line L25 (6.5324, 25.8529) -> (7, 26.1693)
  line L26 (4.0107, 24.1464) -> (3.7942, 24)
  point P0 (0, 0)
  constraints: 24 end point, 24 point on line, 3 collinear, 2 other
extrude "Extrusion12" cut sketch "Skizze11" against normal blind 0.6 contours L24 L7 L25 L12 L26 L8 L19 L17 L20 L9 L21 L14 L22 L10 L23 L1
sketch "Skizze12" plane through (5.2, 0, 0) normal (-1, 0, 0) x (0, 0, 1)
  line L0 (-4.8766, -34.9962) -> (-4.8766, -25.0038) projected
  line L1 (4.6266, -38.084) -> (-4.8766, -34.9962) projected
  line L2 (10.5, -30) -> (4.6266, -38.084) projected
  line L3 (4.6266, -21.916) -> (10.5, -30) projected
  line L4 (-4.8766, -25.0038) -> (4.6266, -21.916) projected
  point P0 (0, 0)
extrude "Extrusion13" cut sketch "Skizze12" against normal blind 0.3
sketch "Skizze13" plane through (8.9, 0, 0) normal (-1, 0, 0) x (0, 0, 1)
  line L0 (3.7942, 36) -> (7, 33.8307) projected
  line L1 (7, 33.8307) -> (7, 35.5) projected
  arc A0 (7, 35.5) -> (6.5, 36) centre (6.5, 35.5) ccw projected
  line L2 (6.5, 36) -> (3.7942, 36) projected
  line L3 (7, 26.1693) -> (3.7942, 24) projected
  line L4 (3.7942, 24) -> (6.5, 24) projected
  arc A1 (6.5, 24) -> (7, 24.5) centre (6.5, 24.5) ccw projected
  line L5 (7, 24.5) -> (7, 26.1693) projected
  line L6 (0.2058, 24) -> (-3, 26.1693) projected
  line L7 (-3, 26.1693) -> (-3, 24.5) projected
  arc A2 (-3, 24.5) -> (-2.5, 24) centre (-2.5, 24.5) ccw projected
  line L8 (-2.5, 24) -> (0.2058, 24) projected
  line L9 (-3, 33.8307) -> (0.2058, 36) projected
  line L10 (0.2058, 36) -> (-2.5, 36) projected
  arc A3 (-2.5, 36) -> (-3, 35.5) centre (-2.5, 35.5) ccw projected
  line L11 (-3, 35.5) -> (-3, 33.8307) projected
  point P0 (0, 0)
extrude "Extrusion14" cut sketch "Skizze13" against normal blind 0.1
equation "\"d4\" = 0.5 * d6"
equation "\"d5\" = d4"
equation "\"d7\" = d8"
equation "\"d9\" = d10"
equation "\"d12\" = -0.5 * d11 + 0.5 * d13"
equation "\"d15\" = d14"
equation "\"d18\" = d17"
equation "\"d28\" = d27"
equation "\"d30\" = d29"
